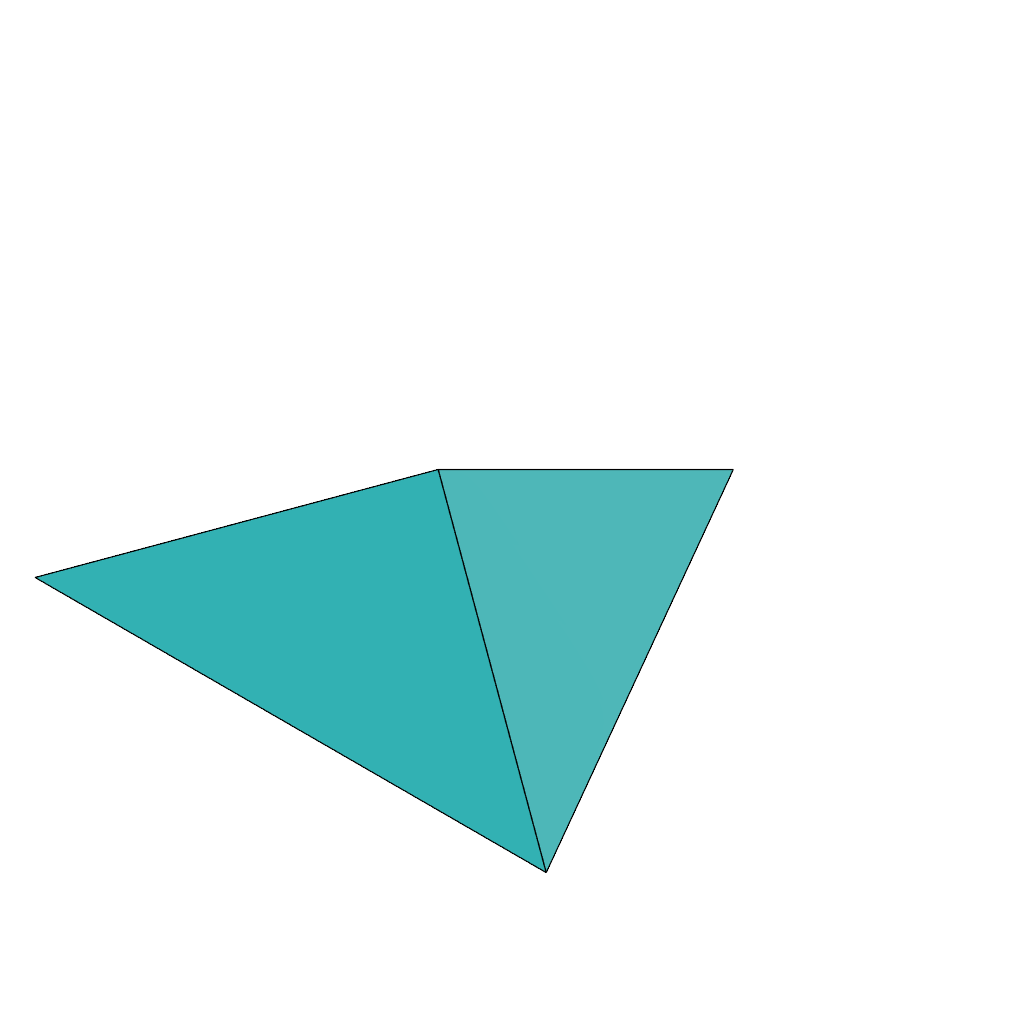
level -1 triangular-based pyramid (Autodesk Fusion 360 design; units mm, degrees)
part number: 2026-10-11-11-42-37-001
Autodesk Fusion 360 part; units mm, degrees
sketch "Sketch1" plane through (0, 0, 0) normal (0, 1, 0) x (1, 0, 0)
  line L0 (-25, 0) -> (25, 0)
  line L1 (25, 0) -> (0, 43.3013)
  line L2 (0, 43.3013) -> (-25, 0)
  point P0 (0, 14.4338)
extrude "Extrude1" add sketch "Sketch1" along normal blind 20 draft -45
